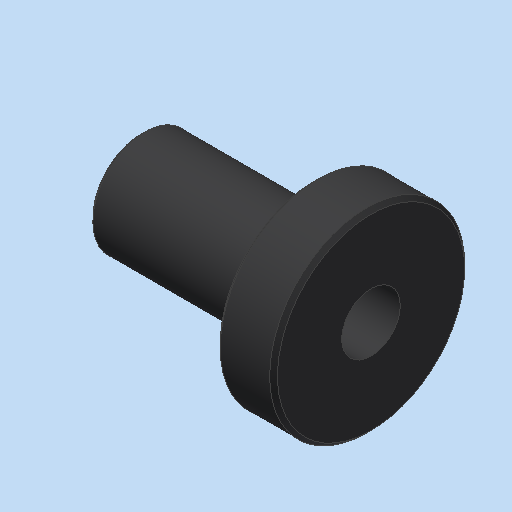
# Autodesk Inventor part: MM0861AN100_G01_122
Saved by Autodesk Inventor 2023.3 (Build 273359000, 359)
## iProperties
Created: 2018-10-29
Part Number: MM0861AN100_G01_122
Material: 1.2379 X155CrVMo 12-1
Document SubType Name: Modeling
Designer: Rose
Density: 7.85 g/cm^3
Appearance: Grün
Description: =<RBPARTNOTITLE2>
Mass: 9.10207 g
Surface Area: 10.8999 cm^2
Volume: 1.1595 cm^3
RBMATERIAL: =<Material>
RBMATNO: =<Part Number>
RBPARTMADEOF: Rd.15x22
RBPARTNOTITLE1: manufactured part
RBPARTNOTITLE2: Anfertigungsteil
MaxAbmaße: 0 x 0 x 0 (FM)
AnP_Material_aktuell: =<Material>
AnP_Kommentar_aktuell: =<Comments>
RBDRAWINGMISSINGSPEC: --
AnP_Kategorie: 1
AnP_Material: =<Material>
RBSURFACE2: HRC 60±2 DyLin beschichtet
Author: Rose
Keywords: =<RBPARTMADEOF>
Comments: =<RBSURFACE2>
Revision Number: 01
Autodesk Inventor part; units mm, degrees
ref_plane "YZ Plane" through (0, 0, 0) normal (1, 0, 0) x (0, 1, 0)
ref_plane "XZ Plane" through (0, 0, 0) normal (0, 1, 0) x (-1, 0, 0)
ref_plane "XY Plane" through (0, 0, 0) normal (0, 0, 1) x (1, 0, 0)
sketch "Skizze1" plane through (0, 0, 0) normal (0, 0, 1) x (1, 0, 0)
  line L0 (0, 9) -> (0, -1.5) projected
  line L1 (-16.84, 0) -> (7.94, 0) projected
  line L2 (-13.3, 0) -> (-13.3, 4)
  line L3 (-13.3, 4) -> (0, 4)
  line L4 (0, 4) -> (0, 7.5)
  line L5 (0, 7.5) -> (4.4, 7.5)
  line L6 (4.4, 7.5) -> (4.4, 0)
  dimension "d0" = 8
  dimension "d1" = 15
  dimension "d2" = 4.4
  dimension "d3" = 13.3
  constraints: 10 end point, 4 perpendicular, 4 point on line
  measures "d0" diameter of L3 L1
  measures "d1" diameter of L5 L1
  measures "d2" distance between parallel lines of L6 L0
  measures "d3" distance of L2.end L3.end
revolve "Umdrehung1" add sketch "Skizze1" angle 360 about axis through (0, 0, 0) along (1, 0, 0)
hole "Bohrung1" at (4.4, 0, 0) direction (-1, 0, 0) diameter 4.5 end through all
chamfer "Fase1" distance 0.3 angle 45 1 edges at (-13.3, -4, 0)
fillet "Rundung1" radius 0.2 1 edges at (0, -4, 0)
chamfer "Fase2" distance 0.3 angle 45 2 edges at (0, -7.5, 0) (4.4, -7.5, 0)
